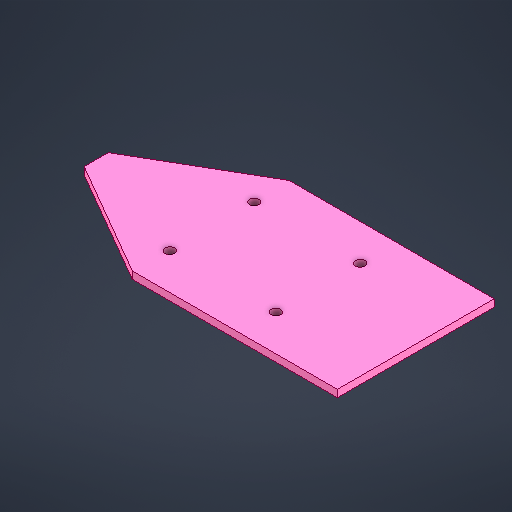
# Autodesk Inventor part: MIENG SAT DE DO
Saved by Autodesk Inventor 2027 (Build 310192060, 192F)
## iProperties
Created: 2026-07-08
Part Number: MIENG SAT DE DO
Material: Generic
Document SubType Name: Modeling
Designer: Laptop
Density: 1 g/cm^3
Appearance: Pink
Author: Laptop
Autodesk Inventor part; units mm, degrees
ref_plane "YZ Plane" through (0, 0, 0) normal (1, 0, 0) x (0, 1, 0)
ref_plane "XZ Plane" through (0, 0, 0) normal (0, 1, 0) x (-1, 0, 0)
ref_plane "XY Plane" through (0, 0, 0) normal (0, 0, 1) x (1, 0, 0)
sketch "Sketch1" plane through (0, 0, 0) normal (0, 1, 0) x (-1, 0, 0)
  line L0 (0, 0) -> (85, 0)
  line L1 (85, -65) -> (0, -65)
  line L2 (0, -65) -> (0, 0)
  line L3 (132.5, -32.5) -> (132.5, -27.5)
  line L4 (132.5, -32.5) -> (132.5, -37.5)
  line L5 (132.5, -37.5) -> (85, -65)
  line L6 (132.5, -27.5) -> (85, 0)
  dimension "d0" = 85
  dimension "d3" = 5
  dimension "d4" = 5
  constraints: 14 end point, 1 horizontal, 1 parallel, 1 vertical
  measures "d0" distance of L1.start L1.end
  measures "d3" distance of L3.start L3.end
  measures "d4" distance of L3.start L4.end
extrude "Extrusion1" add sketch "Sketch1" along normal blind 3
sketch "Sketch2" plane through (0, 3, 0) normal (0, 1, 0) x (1, 0, 0)
  line L0 (-132.5, 37.5) -> (-132.5, 27.5) projected
  circle A0 centre (-40.5, 50) radius 2
  circle A1 centre (-40.5, 15) radius 2
  circle A2 centre (-84.5, 50) radius 2
  circle A3 centre (-84.5, 15) radius 2
  point P0 (0, 0)
  constraints: 4 centre point
extrude "Extrusion2" cut sketch "Sketch2" against normal blind 3
body "Solid1"
